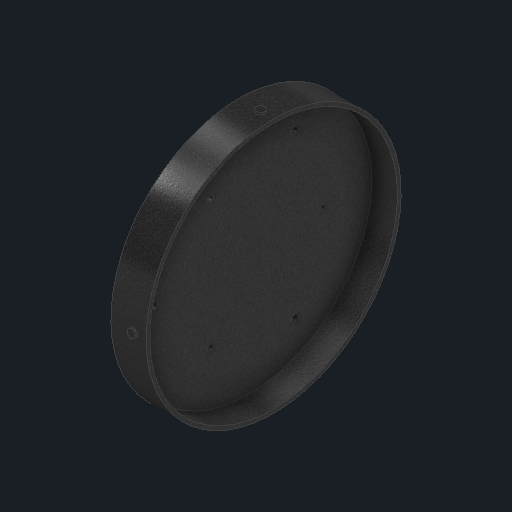
# Autodesk Inventor part: c8n_mirror_cell
Saved by Autodesk Inventor 2027.1 (Build 311270010, 270A)
## iProperties
Created: 2026-11-04
Part Number: c8n_mirror_cell
Material: Generic
Description: C8-N rear mirror cell: sleeve + back plate, 3 collimation + 3 lock holes
Document SubType Name: Modeling
Designer: Claude (from photos)
Density: 1 g/cm^3
Appearance: Black Cast
Author: alexg
Autodesk Inventor part; units mm, degrees
sketch "Cell sleeve sketch" plane through (0, 0, 0) normal (1, 0, 0) x (0, 1, 0)
  circle A0 centre (0, 0) radius 119.5
  circle A1 centre (0, 0) radius 116
  constraints: 2 centre point
extrude "Cell sleeve" add sketch "Cell sleeve sketch" along normal blind 30
sketch "Back plate sketch" plane through (0, 0, 0) normal (1, 0, 0) x (0, 1, 0)
  circle A0 centre (0, 0) radius 116
  constraints: 1 centre point
extrude "Back plate" add sketch "Back plate sketch" along normal blind 6
sketch "Rear rim sketch" plane through (0, 0, 0) normal (1, 0, 0) x (0, 1, 0)
  circle A0 centre (0, 0) radius 119.5
  circle A1 centre (0, 0) radius 105
  constraints: 2 centre point
extrude "Rear rim" add sketch "Rear rim sketch" against normal blind 3
sketch "Collimation + lock holes sketch" plane through (0, 0, 0) normal (1, 0, 0) x (0, 1, 0)
  circle A0 centre (0, 88) radius 3.2
  circle A1 centre (-76.2102, -44) radius 3.2
  circle A2 centre (76.2102, -44) radius 3.2
  circle A3 centre (60.6218, 35) radius 2.7
  circle A4 centre (-60.6218, 35) radius 2.7
  circle A5 centre (0, -70) radius 2.7
  constraints: 6 centre point
extrude "Collimation + lock holes" cut sketch "Collimation + lock holes sketch" along normal blind 6
ref_plane "Work Plane1" through (0, 118, 0) normal (0, 1, 0) x (-1, 0, 0)
sketch "Cell screw top sketch" plane through (0, 118, 0) normal (0, 1, 0) x (-1, 0, 0)
  circle A0 centre (-18, 0) radius 4
  constraints: 1 centre point
extrude "Cell screw top" add sketch "Cell screw top sketch" along normal blind 3.5
ref_plane "Work Plane2" through (0, -118, 0) normal (0, 1, 0) x (-1, 0, 0)
sketch "Cell screw bottom sketch" plane through (0, -118, 0) normal (0, 1, 0) x (-1, 0, 0)
  circle A0 centre (-18, 0) radius 4
  constraints: 1 centre point
extrude "Cell screw bottom" add sketch "Cell screw bottom sketch" against normal blind 3.5
ref_plane "Work Plane3" through (0, 0, 118) normal (0, 0, 1) x (1, 0, 0)
sketch "Cell screw +z sketch" plane through (0, 0, 118) normal (0, 0, 1) x (1, 0, 0)
  circle A0 centre (18, 0) radius 4
  constraints: 1 centre point
extrude "Cell screw +z" add sketch "Cell screw +z sketch" along normal blind 3.5
ref_plane "Work Plane4" through (0, 0, -118) normal (0, 0, 1) x (1, 0, 0)
sketch "Cell screw -z sketch" plane through (0, 0, -118) normal (0, 0, 1) x (1, 0, 0)
  circle A0 centre (18, 0) radius 4
  constraints: 1 centre point
extrude "Cell screw -z" add sketch "Cell screw -z sketch" against normal blind 3.5
body "Solid1"
